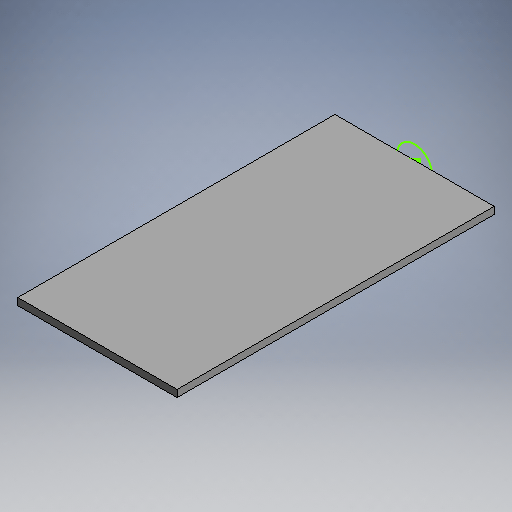
# Autodesk Inventor part: Speed_Roll_Door
Saved by Autodesk Inventor 2026.2 (Build 302298000, 298)
## iProperties
Part Number: Speed_Roll_Door
Material: Generic
Document SubType Name: Modeling
Designer: Jacob
Appearance: Default
Author: Jacob
Autodesk Inventor part; units mm, degrees
ref_plane "YZ Plane" through (0, 0, 0) normal (1, 0, 0) x (0, 1, 0)
ref_plane "XZ Plane" through (0, 0, 0) normal (0, 1, 0) x (-1, 0, 0)
ref_plane "XY Plane" through (0, 0, 0) normal (0, 0, 1) x (1, 0, 0)
sketch "Sketch1" plane through (0, 0, 0) normal (0, 0, 1) x (1, 0, 0)
  line L0 (-1130, -50) -> (1130, -50)
  line L1 (1130, -50) -> (1130, 50)
  line L2 (1130, 50) -> (-1130, 50)
  line L3 (-1130, 50) -> (-1130, -50)
  constraints: 8 end point, 2 parallel, 1 horizontal, 1 perpendicular
extrude "Extrusion1" add sketch "Sketch1" along normal blind 4500
sketch "Sketch2" plane through (0, 0, 0) normal (0, 0, 1) x (1, 0, 0)
  circle A0 centre (0, 0) radius 250
  constraints: 1 centre point
body "Solid1"
